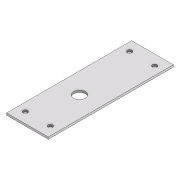
# Autodesk Inventor part: Rotorschutz_SL_BT2
Saved by Autodesk Inventor 2020.1 (Build 241239000, 239)
## iProperties
Created: 2020-08-20
Part Number: Rotorschutz_SL_BT2
Material: Generisch
Document SubType Name: Modeling
Designer: s5chfeis
Density: 1 g/cm^3
Appearance: Vorgabe
Author: s5chfeis
Autodesk Inventor part; units mm, degrees
ref_plane "YZ Plane" through (0, 0, 0) normal (1, 0, 0) x (0, 1, 0)
ref_plane "XZ Plane" through (0, 0, 0) normal (0, 1, 0) x (-1, 0, 0)
ref_plane "XY Plane" through (0, 0, 0) normal (0, 0, 1) x (1, 0, 0)
sketch "Skizze1" plane through (0, 0, 0) normal (0, 1, 0) x (-1, 0, 0)
  line L0 (0, 0) -> (-100, 0)
  line L1 (-100, 0) -> (-100, 300)
  line L2 (-100, 300) -> (0, 300)
  line L3 (0, 300) -> (0, 0)
  dimension "d0" = 100
  dimension "d1" = 300
  constraints: 8 end point, 2 parallel, 1 horizontal, 1 perpendicular
  measures "d0" distance of L1.end L2.end
  measures "d1" distance of L0.end L1.end
extrude "Extrusion1" add sketch "Skizze1" along normal blind 5
sketch "Skizze2" plane through (0, 5, 0) normal (0, 1, 0) x (1, 0, 0)
  line L0 (0, -300) -> (100, -300) construction
  line L1 (50, -300) -> (50, -100) construction
  line L2 (50, -300) -> (250, -300) construction
  line L3 (100, -300) -> (100, -175) construction
  line L4 (100, -300) -> (100, 0) construction
  line L5 (100, -300) -> (225, -300) construction
  line L6 (100, -175) -> (0, -175) construction
  line L7 (0, 0) -> (0, -300) construction
  circle A0 centre (50, -175) radius 14
  dimension "d4" = 200
  dimension "d5" = 90
  dimension "d6" = 125
  dimension "d7" = 90
  dimension "d8" = 100
  dimension "d9" = 90
  dimension "d10" = 28
  constraints: 10 end point, 3 perpendicular, 2 horizontal, 2 midpoint, 1 centre point, 1 collinear, 1 vertical
  measures "d4" distance of L1.start L1.end
  measures "d5" angle of L2 L1
  measures "d6" distance of L0.end L3.end
  measures "d7" angle of L5 L3
  measures "d8" distance of L3.end L6.end
  measures "d9" angle of L6 L3
  measures "d10" diameter of A0
extrude "Extrusion2" cut sketch "Skizze2" against normal blind 10
sketch "Skizze3" plane through (0, 5, 0) normal (0, 1, 0) x (1, 0, 0)
  line L0 (0, 0) -> (0, -25) construction
  line L1 (0, 0) -> (25, 0) construction
  line L2 (0, -25) -> (20, -25) construction
  line L3 (20, -25) -> (80, -25) construction
  line L4 (0, -300) -> (100, -300) construction
  line L5 (0, -300) -> (0, -275) construction
  line L6 (0, -300) -> (25, -300) construction
  line L7 (0, -275) -> (20, -275) construction
  line L8 (20, -275) -> (80, -275) construction
  dimension "d13" = 25
  dimension "d14" = 90
  dimension "d15" = 20
  dimension "d16" = 60
  dimension "d17" = 180
  dimension "d18" = 25
  dimension "d19" = 90
  dimension "d20" = 20
  dimension "d21" = 90
  dimension "d22" = 60
  dimension "d23" = 180
  constraints: 16 end point, 5 coincident, 4 perpendicular, 2 collinear, 2 horizontal, 2 vertical
  measures "d13" distance of L0.start L0.end
  measures "d14" angle of L0 L1
  measures "d15" distance of L0.end L2.end
  measures "d16" distance of L2.end L3.end
  measures "d17" angle of L3 L2
  measures "d18" distance of L4.start L5.end
  measures "d19" angle of L6 L5
  measures "d20" distance of L5.end L7.end
  measures "d21" angle of L5 L7
  measures "d22" distance of L7.end L8.end
  measures "d23" angle of L8 L7
hole "Bohrung1" at (20, 5, 25) at (80, 5, 25) at (20, 5, 275) at (80, 5, 275) direction (0, -1, 0) diameter 11 depth 27.3 tip angle 118
